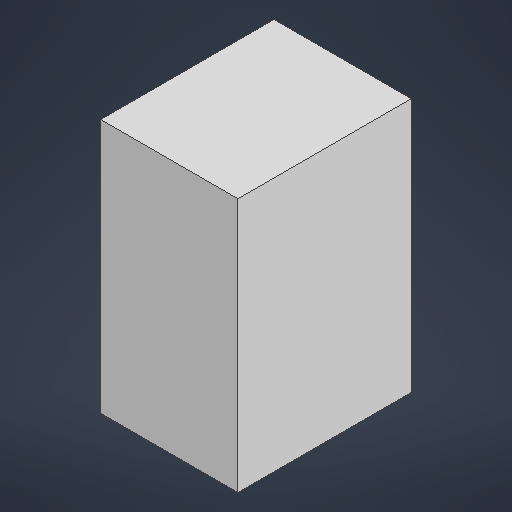
# Autodesk Inventor part: Part1
Saved by Autodesk Inventor 2026 (Build 300175000, 175)
## iProperties
Created: 2025-12-18
Part Number: Part1
Material: Generic
Document SubType Name: Modeling
Designer: MSI NOTEBOOK
Density: 1 g/cm^3
Appearance: Default
Author: MSI NOTEBOOK
Autodesk Inventor part; units mm, degrees
ref_plane "YZ Plane" through (0, 0, 0) normal (1, 0, 0) x (0, 1, 0)
ref_plane "XZ Plane" through (0, 0, 0) normal (0, 1, 0) x (-1, 0, 0)
ref_plane "XY Plane" through (0, 0, 0) normal (0, 0, 1) x (1, 0, 0)
sketch "Sketch1" plane through (0, 0, 0) normal (0, 1, 0) x (-1, 0, 0)
  line L0 (4.045, 5.1088) -> (-4.045, 5.1088)
  line L1 (-4.045, 5.1088) -> (-4.045, -5.1088)
  line L2 (-4.045, -5.1088) -> (4.045, -5.1088)
  line L3 (4.045, -5.1088) -> (4.045, 5.1088)
  line L4 (4.045, 5.1088) -> (-4.045, -5.1088) construction
  line L5 (-4.045, 5.1088) -> (4.045, -5.1088) construction
  point P0 (0, 0)
  dimension "d2" = 8.09
  constraints: 12 end point, 2 midpoint, 2 parallel, 1 horizontal, 1 perpendicular
  measures "d2" distance of L1.end L2.end
extrude "Extrusion1" add sketch "Sketch1" along normal blind 15
body "Solid1"
